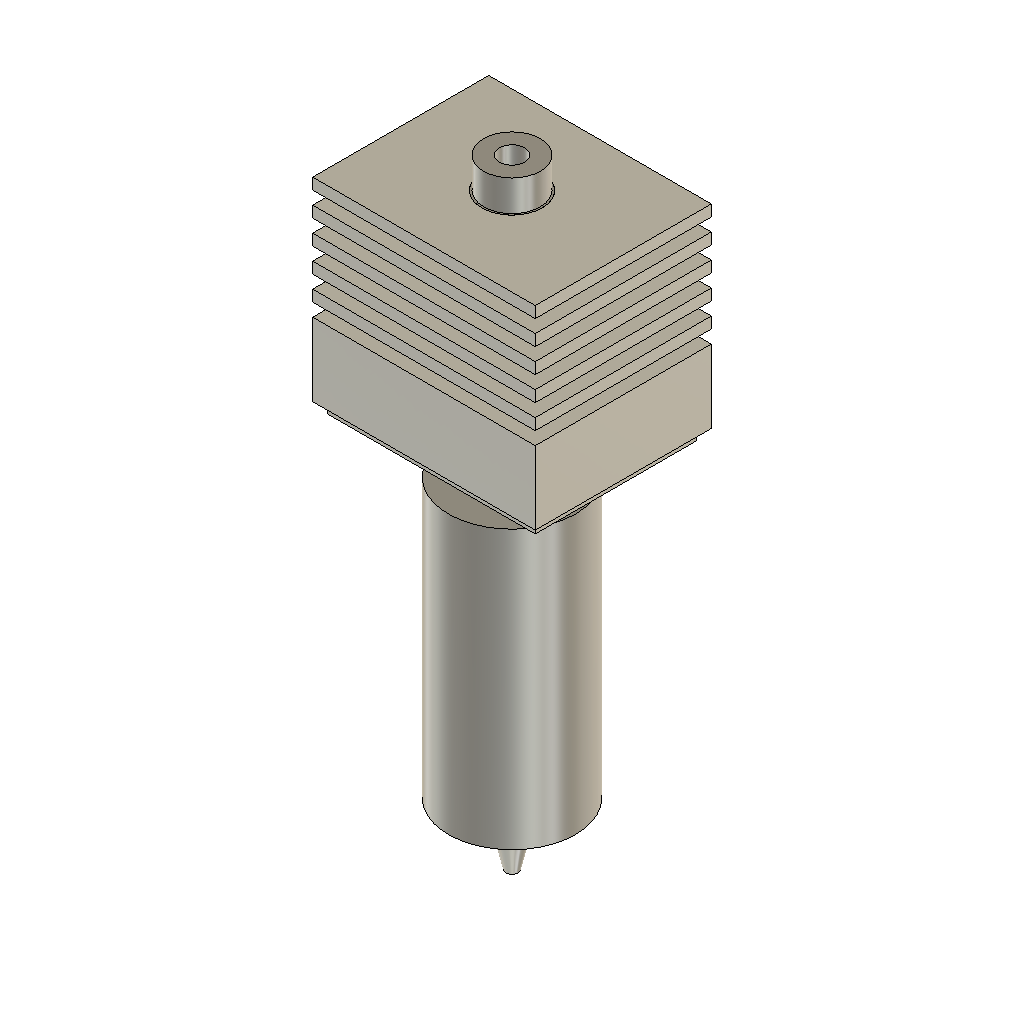
bambu_hotend_stock (Autodesk Fusion 360 design; units mm, degrees)
part number: 2026-11-20-19-03-50-397
Autodesk Fusion 360 part; units mm, degrees
sketch "Sketch1" plane through (0, 0, 0) normal (0, 1, 0) x (1, 0, 0)
  line L0 (0.2, 0) -> (0.5, 0)
  line L1 (0.5, 0) -> (1.15, -2.82)
  line L2 (1.15, -2.82) -> (5.05, -4.91)
  line L3 (5.05, -4.91) -> (5.05, -26.99)
  line L4 (5.05, -26.99) -> (1, -26.99)
  line L5 (1, -26.99) -> (1, -3)
  line L6 (1, -3) -> (0.2, -2)
  line L7 (0.2, -2) -> (0.2, 0)
revolve "Revolve1" add sketch "Sketch1" angle 360 about axis through (0, 0, 1.75) along (0, 0, 1) makes body 1
sketch "Sketch2" plane through (0, 0, 0) normal (0, 1, 0) x (1, 0, 0)
  line L0 (1, -26.99) -> (2.4, -26.99)
  line L1 (2.4, -26.99) -> (2.4, -46.75)
  line L2 (2.4, -46.75) -> (2.25, -46.75)
  line L3 (2.25, -46.75) -> (2.25, -49.2)
  line L4 (2.25, -49.2) -> (1, -49.2)
  line L5 (1, -49.2) -> (1, -26.99)
revolve "Revolve2" add sketch "Sketch2" angle 360 about axis through (0, 0, 1.75) along (0, 0, 1) separate body makes body 2
ref_plane "WorkPlane1" through (0, 0, 30.42) normal (0, 0, 1) x (1, 0, 0)
sketch "Sketch3" plane through (0, 0, 30.42) normal (0, 0, 1) x (1, 0, 0)
  line L0 (8.25, 6.4) -> (-8.25, 6.4)
  line L1 (-8.25, 6.4) -> (-8.25, -6.4)
  line L2 (-8.25, -6.4) -> (8.25, -6.4)
  line L3 (8.25, -6.4) -> (8.25, 6.4)
  circle A0 centre (0, 0) radius 2.4
extrude "Extrude1" add sketch "Sketch3" along normal blind 0.86 separate body makes body 3
ref_plane "WorkPlane2" through (0, 0, 31.28) normal (0, 0, 1) x (1, 0, 0)
sketch "Sketch4" plane through (0, 0, 31.28) normal (0, 0, 1) x (1, 0, 0)
  line L0 (8.85, 7) -> (-8.85, 7)
  line L1 (-8.85, 7) -> (-8.85, -7)
  line L2 (-8.85, -7) -> (8.85, -7)
  line L3 (8.85, -7) -> (8.85, 7)
  circle A0 centre (0, 0) radius 2.4
extrude "Extrude2" add sketch "Sketch4" along normal blind 15.47 bodies 3
ref_plane "WorkPlane3" through (0, 0, 44.82) normal (0, 0, 1) x (1, 0, 0)
sketch "Sketch5" plane through (0, 0, 44.82) normal (0, 0, 1) x (1, 0, 0)
  line L0 (9.85, 8) -> (-9.85, 8)
  line L1 (-9.85, 8) -> (-9.85, -8)
  line L2 (-9.85, -8) -> (9.85, -8)
  line L3 (9.85, -8) -> (9.85, 8)
  circle A0 centre (0, 0) radius 4
extrude "Extrude3" cut sketch "Sketch5" along normal blind 1.03 bodies 3
ref_plane "WorkPlane4" through (0, 0, 42.89) normal (0, 0, 1) x (1, 0, 0)
sketch "Sketch6" plane through (0, 0, 42.89) normal (0, 0, 1) x (1, 0, 0)
  line L0 (9.85, 8) -> (-9.85, 8)
  line L1 (-9.85, 8) -> (-9.85, -8)
  line L2 (-9.85, -8) -> (9.85, -8)
  line L3 (9.85, -8) -> (9.85, 8)
  circle A0 centre (0, 0) radius 4
extrude "Extrude4" cut sketch "Sketch6" along normal blind 1.03 bodies 3
ref_plane "WorkPlane5" through (0, 0, 40.96) normal (0, 0, 1) x (1, 0, 0)
sketch "Sketch7" plane through (0, 0, 40.96) normal (0, 0, 1) x (1, 0, 0)
  line L0 (9.85, 8) -> (-9.85, 8)
  line L1 (-9.85, 8) -> (-9.85, -8)
  line L2 (-9.85, -8) -> (9.85, -8)
  line L3 (9.85, -8) -> (9.85, 8)
  circle A0 centre (0, 0) radius 4
extrude "Extrude5" cut sketch "Sketch7" along normal blind 1.03 bodies 3
ref_plane "WorkPlane6" through (0, 0, 39.03) normal (0, 0, 1) x (1, 0, 0)
sketch "Sketch8" plane through (0, 0, 39.03) normal (0, 0, 1) x (1, 0, 0)
  line L0 (9.85, 8) -> (-9.85, 8)
  line L1 (-9.85, 8) -> (-9.85, -8)
  line L2 (-9.85, -8) -> (9.85, -8)
  line L3 (9.85, -8) -> (9.85, 8)
  circle A0 centre (0, 0) radius 4
extrude "Extrude6" cut sketch "Sketch8" along normal blind 1.03 bodies 3
ref_plane "WorkPlane7" through (0, 0, 37.1) normal (0, 0, 1) x (1, 0, 0)
sketch "Sketch9" plane through (0, 0, 37.1) normal (0, 0, 1) x (1, 0, 0)
  line L0 (9.85, 8) -> (-9.85, 8)
  line L1 (-9.85, 8) -> (-9.85, -8)
  line L2 (-9.85, -8) -> (9.85, -8)
  line L3 (9.85, -8) -> (9.85, 8)
  circle A0 centre (0, 0) radius 4
extrude "Extrude7" cut sketch "Sketch9" along normal blind 1.03 bodies 3
named bodies: "Nozzle", "HeatBreak", "Heatsink"
